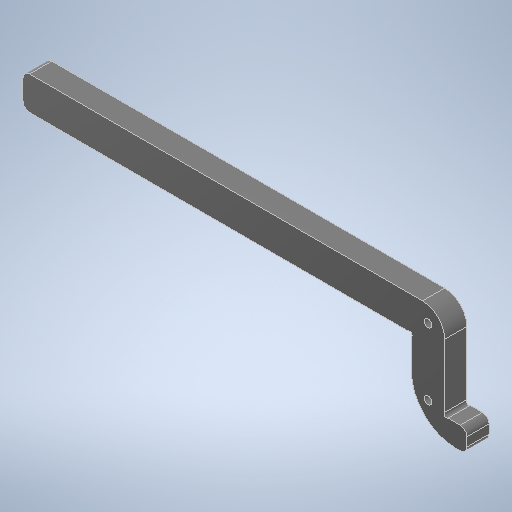
# Autodesk Inventor part: AP5.0_PC-stand-spacer
Saved by Autodesk Inventor 2025.3 (Build 293356030, 356C)
## iProperties
Created: 2025-08-02
Part Number: AP5.0_PC-stand-spacer
Material: 一般
Document SubType Name: Sheet Metal
Designer: ibuki_ono
Density: 1 g/cm^3
Sheet Metal Rule: Default
Appearance: 滑らか - 黒
Author: ibuki_ono
## iProperties of the stored document AP5.0_PC-stand-spacer_3D プリント.ipt
Created: 2025-09-13
Part Number: AP5.0_PC-stand-spacer_3D プリント
Material: 一般
Document SubType Name: Modeling
Designer: ibuki_ono
Density: 1 g/cm^3
Appearance: 既定
Author: ibuki_ono
Autodesk Inventor part; units mm, degrees
ref_plane "YZ Plane" through (0, 0, 0) normal (1, 0, 0) x (0, 1, 0)
ref_plane "XZ Plane" through (0, 0, 0) normal (0, 1, 0) x (-1, 0, 0)
ref_plane "XY Plane" through (0, 0, 0) normal (0, 0, 1) x (1, 0, 0)
sketch "スケッチ1" plane through (0, 0, 0) normal (0, 0, 1) x (1, 0, 0)
  line L0 (-95, -7.5) -> (95, -7.5)
  line L1 (95, -7.5) -> (95, 7.5)
  line L2 (95, 7.5) -> (-95, 7.5)
  line L3 (-95, 7.5) -> (-95, -7.5)
  line L4 (-95, -7.5) -> (95, 7.5) construction
  line L5 (95, -7.5) -> (-95, 7.5) construction
  line L6 (95, 7.5) -> (80, 7.5)
  line L7 (80, 7.5) -> (80, -32.5)
  line L8 (80, -32.5) -> (95, -32.5)
  line L9 (95, -32.5) -> (95, 7.5)
  line L10 (80, -32.5) -> (105, -32.5)
  line L11 (105, -32.5) -> (105, -42.5)
  line L12 (105, -42.5) -> (80, -42.5)
  line L13 (80, -42.5) -> (80, -32.5)
  point P0 (0, 0)
  point P1 (80, -7.5)
  point P2 (95, -32.5)
  dimension "d0" = 190
  dimension "d1" = 15
  dimension "d2" = 15
  dimension "d3" = 40
  dimension "d4" = 25
  dimension "d5" = 10
  constraints: 28 end point, 6 parallel, 3 horizontal, 3 perpendicular, 2 midpoint
  measures "d0" distance of L2.end L1.end
  measures "d1" distance of L1.end L0.end
  measures "d2" distance of L8.end L7.end
  measures "d3" distance of L7.end L6.end
  measures "d4" distance of L11.end L12.end
  measures "d5" distance of L10.end L11.end
extrude "押し出し1" add sketch "スケッチ1" along normal blind 10
fillet "フィレット1" radius 20 1 edges at (80, -42.5, 5)
sketch "スケッチ3" plane through (0, 0, 10) normal (0, 0, 1) x (1, 0, 0)
  arc A0 (80, -22.5) -> (100, -42.5) centre (100, -22.5) ccw projected
  line L0 (100, -42.5) -> (105, -42.5) projected
  line L1 (105, -42.5) -> (105, -32.5) projected
  line L2 (105, -32.5) -> (95, -32.5) projected
  line L3 (95, -32.5) -> (95, 7.5) projected
  line L4 (95, 7.5) -> (-95, 7.5) projected
  line L5 (-95, 7.5) -> (-95, -7.5) projected
  line L6 (-95, -7.5) -> (80, -7.5) projected
  line L7 (80, -7.5) -> (80, -22.5) projected
  line L8 (-95, -7.5) -> (80, -7.5) projected
  line L9 (80, -7.5) -> (79.2575, -8.2425) construction
  line L10 (80, -7.5) -> (81.05, -7.5) construction
  circle A1 centre (79.2575, -8.2425) radius 1.05
  line L11 (105, -32.5) -> (95, -32.5) projected
  line L12 (95, -32.5) -> (95, 7.5) projected
  line L13 (95, -32.5) -> (95.7425, -31.7575)
  line L14 (95, -32.5) -> (96.05, -32.5) construction
  circle A2 centre (95.7425, -31.7575) radius 1.05
  point P0 (0, 0)
  dimension "d19" = 1.05
  dimension "d20" = 135
  dimension "d37" = 1.05
  dimension "d38" = 45
  constraints: 8 end point, 2 coincident, 2 equal length, 2 horizontal, 6 other
  measures "d19" distance of L6.end L9.end
  measures "d20" angle of L9 L10
  measures "d37" distance of L2.end L13.end
  measures "d38" angle of L14 L13
extrude "押し出し2" cut sketch "スケッチ3" against normal through all contours A1 L6 L7 | L7 A1 | L6 A1 | A2 L2 | L2 L3 A2 | A2 L3
fillet "フィレット3" radius 3 4 edges at (105, -32.5, 5) (105, -42.5, 5) (-95, -7.5, 5) (-95, 7.5, 5)
fillet "フィレット4" radius 10 1 edges at (95, 7.5, 5)
sketch "スケッチ4" plane through (0, 0, 10) normal (0, 0, 1) x (1, 0, 0)
  line L0 (87.5, 0) -> (87.5, -30) construction
  line L1 (87.5, 0) -> (117.5, 0) construction
  line L2 (85, 7.5) -> (-92, 7.5) construction
  line L3 (95, -32.5) -> (95, -2.5) construction
  point P0 (0, 0)
  point P1 (125, -30.5)
  dimension "d26" = 30
  dimension "d27" = 90
  dimension "d28" = 7.5
  dimension "d29" = 7.5
  constraints: 4 end point, 2 coincident, 1 horizontal, 1 perpendicular, 1 vertical, 1 other
  measures "d26" distance of L0.start L0.end
  measures "d27" angle of L0 L1
  measures "d28" distance from line of L2 L0.start
hole "穴2" at (87.5, 0, 10) at (87.5, -30, 10) direction (0, 0, -1) diameter 3.5 end through all
equation "\"d29\" = d28"
equation "\"d35\" = Thickness"
equation "\"BendRadius\" = Thickness"
equation "\"BendReliefWidth\" = Thickness"
equation "\"BendReliefDepth\" = 0.5 * Thickness"
equation "\"TransitionRadius\" = BendRadius"
equation "\"JacobiRadiusSize\" = BendRadius"
equation "\"GapSize\" = Thickness"
equation "\"Thickness\" = 5"
